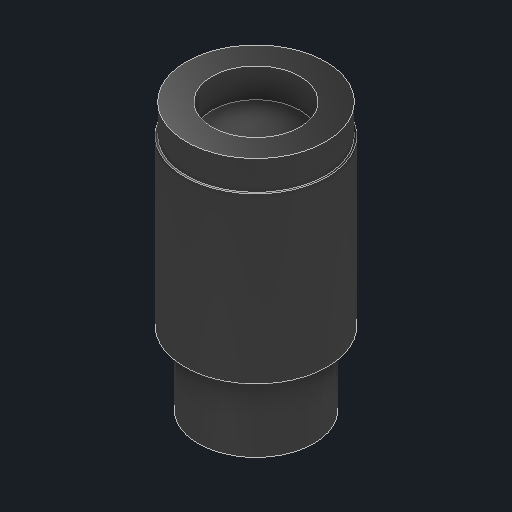
# Autodesk Inventor part: c8n_eyepiece_25mm
Saved by Autodesk Inventor 2027.1 (Build 311270010, 270A)
## iProperties
Created: 2026-11-04
Part Number: c8n_eyepiece_25mm
Material: Generic
Description: 25 mm 1.25 in eyepiece
Document SubType Name: Modeling
Designer: Claude (from photos)
Density: 1 g/cm^3
Appearance: Glossy - Black
Author: alexg
Autodesk Inventor part; units mm, degrees
ref_plane "Work Plane1" through (0, 205, 0) normal (0, 1, 0) x (-1, 0, 0)
sketch "Barrel 1.25 sketch" plane through (0, 205, 0) normal (0, 1, 0) x (-1, 0, 0)
  circle A0 centre (-842, 0) radius 15.8
  constraints: 1 centre point
extrude "Barrel 1.25" add sketch "Barrel 1.25 sketch" along normal blind 20
ref_plane "Work Plane2" through (0, 225, 0) normal (0, 1, 0) x (-1, 0, 0)
sketch "Body sketch" plane through (0, 225, 0) normal (0, 1, 0) x (-1, 0, 0)
  circle A0 centre (-842, 0) radius 19.5
  constraints: 1 centre point
extrude "Body" add sketch "Body sketch" along normal blind 45
ref_plane "Work Plane3" through (0, 270, 0) normal (0, 1, 0) x (-1, 0, 0)
sketch "Eyecup sketch" plane through (0, 270, 0) normal (0, 1, 0) x (-1, 0, 0)
  circle A0 centre (-842, 0) radius 19
  circle A1 centre (-842, 0) radius 12
  constraints: 2 centre point
extrude "Eyecup" add sketch "Eyecup sketch" along normal blind 8
body "Solid1"
